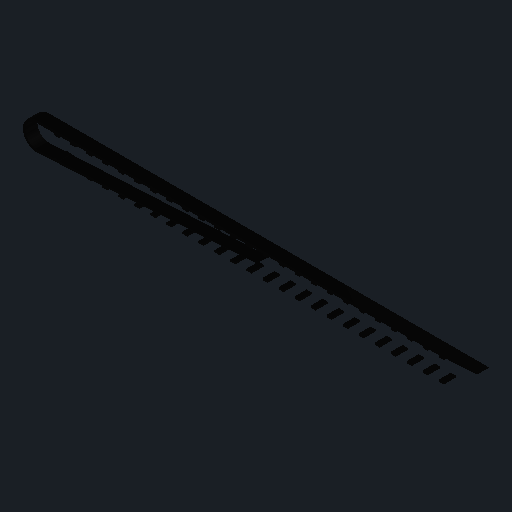
# Autodesk Inventor part: Cinta_Transportadora_20mm_L500
Saved by Autodesk Inventor 2027.2 (Build 312334000, 334)
## iProperties
Part Number: Cinta_Transportadora_20mm_L500
Material: Genérico
Document SubType Name: Modelado
Designer: Usuario
Appearance: Por defecto
Author: Usuario
Autodesk Inventor part; units mm, degrees
ref_plane "Plano YZ" through (0, 0, 0) normal (1, 0, 0) x (0, 1, 0)
ref_plane "Plano XZ" through (0, 0, 0) normal (0, 1, 0) x (-1, 0, 0)
ref_plane "Plano XY" through (0, 0, 0) normal (0, 0, 1) x (1, 0, 0)
sketch "Boceto1" plane through (0, 0, 0) normal (0, 0, 1) x (1, 0, 0)
  line L0 (-220, 14) -> (220, 14)
  arc A0 (220, -14) -> (220, 14) centre (220, 0) ccw
  line L1 (220, 14) -> (-220, -14)
  arc A1 (-220, 14) -> (-220, -14) centre (-220, 0) ccw
  constraints: 4 end point, 4 point on circle, 2 centre point
extrude "Extrusión1" add sketch "Boceto1" along normal mid plane 12
sketch "Boceto2" plane through (0, 0, 0) normal (0, 0, 1) x (1, 0, 0)
  line L0 (-220, 11.5) -> (220, 11.5)
  arc A0 (220, -11.5) -> (220, 11.5) centre (220, 0) ccw
  line L1 (220, 11.5) -> (-220, -11.5)
  arc A1 (-220, 11.5) -> (-220, -11.5) centre (-220, 0) ccw
  constraints: 4 end point, 4 point on circle, 2 centre point
extrude "Extrusión2" cut sketch "Boceto2" along normal mid plane 12
sketch "Boceto3" plane through (0, 0, 0) normal (0, 0, 1) x (1, 0, 0)
  line L0 (-202.5, -11.5) -> (-197.5, -11.5)
  line L1 (-197.5, -11.5) -> (-197.5, -9.7)
  line L2 (-197.5, -9.7) -> (-202.5, -9.7)
  line L3 (-202.5, -9.7) -> (-202.5, -11.5)
  line L4 (-202.5, 9.7) -> (-197.5, 9.7)
  line L5 (-197.5, 9.7) -> (-197.5, 11.5)
  line L6 (-197.5, 11.5) -> (-202.5, 11.5)
  line L7 (-202.5, 11.5) -> (-202.5, 9.7)
  line L8 (-186.5, -11.5) -> (-181.5, -11.5)
  line L9 (-181.5, -11.5) -> (-181.5, -9.7)
  line L10 (-181.5, -9.7) -> (-186.5, -9.7)
  line L11 (-186.5, -9.7) -> (-186.5, -11.5)
  line L12 (-186.5, 9.7) -> (-181.5, 9.7)
  line L13 (-181.5, 9.7) -> (-181.5, 11.5)
  line L14 (-181.5, 11.5) -> (-186.5, 11.5)
  line L15 (-186.5, 11.5) -> (-186.5, 9.7)
  line L16 (-170.5, -11.5) -> (-165.5, -11.5)
  line L17 (-165.5, -11.5) -> (-165.5, -9.7)
  line L18 (-165.5, -9.7) -> (-170.5, -9.7)
  line L19 (-170.5, -9.7) -> (-170.5, -11.5)
  line L20 (-170.5, 9.7) -> (-165.5, 9.7)
  line L21 (-165.5, 9.7) -> (-165.5, 11.5)
  line L22 (-165.5, 11.5) -> (-170.5, 11.5)
  line L23 (-170.5, 11.5) -> (-170.5, 9.7)
  line L24 (-154.5, -11.5) -> (-149.5, -11.5)
  line L25 (-149.5, -11.5) -> (-149.5, -9.7)
  line L26 (-149.5, -9.7) -> (-154.5, -9.7)
  line L27 (-154.5, -9.7) -> (-154.5, -11.5)
  line L28 (-154.5, 9.7) -> (-149.5, 9.7)
  line L29 (-149.5, 9.7) -> (-149.5, 11.5)
  line L30 (-149.5, 11.5) -> (-154.5, 11.5)
  line L31 (-154.5, 11.5) -> (-154.5, 9.7)
  line L32 (-138.5, -11.5) -> (-133.5, -11.5)
  line L33 (-133.5, -11.5) -> (-133.5, -9.7)
  line L34 (-133.5, -9.7) -> (-138.5, -9.7)
  line L35 (-138.5, -9.7) -> (-138.5, -11.5)
  line L36 (-138.5, 9.7) -> (-133.5, 9.7)
  line L37 (-133.5, 9.7) -> (-133.5, 11.5)
  line L38 (-133.5, 11.5) -> (-138.5, 11.5)
  line L39 (-138.5, 11.5) -> (-138.5, 9.7)
  line L40 (-122.5, -11.5) -> (-117.5, -11.5)
  line L41 (-117.5, -11.5) -> (-117.5, -9.7)
  line L42 (-117.5, -9.7) -> (-122.5, -9.7)
  line L43 (-122.5, -9.7) -> (-122.5, -11.5)
  line L44 (-122.5, 9.7) -> (-117.5, 9.7)
  line L45 (-117.5, 9.7) -> (-117.5, 11.5)
  line L46 (-117.5, 11.5) -> (-122.5, 11.5)
  line L47 (-122.5, 11.5) -> (-122.5, 9.7)
  line L48 (-106.5, -11.5) -> (-101.5, -11.5)
  line L49 (-101.5, -11.5) -> (-101.5, -9.7)
  line L50 (-101.5, -9.7) -> (-106.5, -9.7)
  line L51 (-106.5, -9.7) -> (-106.5, -11.5)
  line L52 (-106.5, 9.7) -> (-101.5, 9.7)
  line L53 (-101.5, 9.7) -> (-101.5, 11.5)
  line L54 (-101.5, 11.5) -> (-106.5, 11.5)
  line L55 (-106.5, 11.5) -> (-106.5, 9.7)
  line L56 (-90.5, -11.5) -> (-85.5, -11.5)
  line L57 (-85.5, -11.5) -> (-85.5, -9.7)
  line L58 (-85.5, -9.7) -> (-90.5, -9.7)
  line L59 (-90.5, -9.7) -> (-90.5, -11.5)
  line L60 (-90.5, 9.7) -> (-85.5, 9.7)
  line L61 (-85.5, 9.7) -> (-85.5, 11.5)
  line L62 (-85.5, 11.5) -> (-90.5, 11.5)
  line L63 (-90.5, 11.5) -> (-90.5, 9.7)
  line L64 (-74.5, -11.5) -> (-69.5, -11.5)
  line L65 (-69.5, -11.5) -> (-69.5, -9.7)
  line L66 (-69.5, -9.7) -> (-74.5, -9.7)
  line L67 (-74.5, -9.7) -> (-74.5, -11.5)
  line L68 (-74.5, 9.7) -> (-69.5, 9.7)
  line L69 (-69.5, 9.7) -> (-69.5, 11.5)
  line L70 (-69.5, 11.5) -> (-74.5, 11.5)
  line L71 (-74.5, 11.5) -> (-74.5, 9.7)
  line L72 (-58.5, -11.5) -> (-53.5, -11.5)
  line L73 (-53.5, -11.5) -> (-53.5, -9.7)
  line L74 (-53.5, -9.7) -> (-58.5, -9.7)
  line L75 (-58.5, -9.7) -> (-58.5, -11.5)
  line L76 (-58.5, 9.7) -> (-53.5, 9.7)
  line L77 (-53.5, 9.7) -> (-53.5, 11.5)
  line L78 (-53.5, 11.5) -> (-58.5, 11.5)
  line L79 (-58.5, 11.5) -> (-58.5, 9.7)
  line L80 (-42.5, -11.5) -> (-37.5, -11.5)
  line L81 (-37.5, -11.5) -> (-37.5, -9.7)
  line L82 (-37.5, -9.7) -> (-42.5, -9.7)
  line L83 (-42.5, -9.7) -> (-42.5, -11.5)
  line L84 (-42.5, 9.7) -> (-37.5, 9.7)
  line L85 (-37.5, 9.7) -> (-37.5, 11.5)
  line L86 (-37.5, 11.5) -> (-42.5, 11.5)
  line L87 (-42.5, 11.5) -> (-42.5, 9.7)
  line L88 (-26.5, -11.5) -> (-21.5, -11.5)
  line L89 (-21.5, -11.5) -> (-21.5, -9.7)
  line L90 (-21.5, -9.7) -> (-26.5, -9.7)
  line L91 (-26.5, -9.7) -> (-26.5, -11.5)
  line L92 (-26.5, 9.7) -> (-21.5, 9.7)
  line L93 (-21.5, 9.7) -> (-21.5, 11.5)
  line L94 (-21.5, 11.5) -> (-26.5, 11.5)
  line L95 (-26.5, 11.5) -> (-26.5, 9.7)
  line L96 (-10.5, -11.5) -> (-5.5, -11.5)
  line L97 (-5.5, -11.5) -> (-5.5, -9.7)
  line L98 (-5.5, -9.7) -> (-10.5, -9.7)
  line L99 (-10.5, -9.7) -> (-10.5, -11.5)
  line L100 (-10.5, 9.7) -> (-5.5, 9.7)
  line L101 (-5.5, 9.7) -> (-5.5, 11.5)
  line L102 (-5.5, 11.5) -> (-10.5, 11.5)
  line L103 (-10.5, 11.5) -> (-10.5, 9.7)
  line L104 (5.5, -11.5) -> (10.5, -11.5)
  line L105 (10.5, -11.5) -> (10.5, -9.7)
  line L106 (10.5, -9.7) -> (5.5, -9.7)
  line L107 (5.5, -9.7) -> (5.5, -11.5)
  line L108 (5.5, 9.7) -> (10.5, 9.7)
  line L109 (10.5, 9.7) -> (10.5, 11.5)
  line L110 (10.5, 11.5) -> (5.5, 11.5)
  line L111 (5.5, 11.5) -> (5.5, 9.7)
  line L112 (21.5, -11.5) -> (26.5, -11.5)
  line L113 (26.5, -11.5) -> (26.5, -9.7)
  line L114 (26.5, -9.7) -> (21.5, -9.7)
  line L115 (21.5, -9.7) -> (21.5, -11.5)
  line L116 (21.5, 9.7) -> (26.5, 9.7)
  line L117 (26.5, 9.7) -> (26.5, 11.5)
  line L118 (26.5, 11.5) -> (21.5, 11.5)
  line L119 (21.5, 11.5) -> (21.5, 9.7)
  line L120 (37.5, -11.5) -> (42.5, -11.5)
  line L121 (42.5, -11.5) -> (42.5, -9.7)
  line L122 (42.5, -9.7) -> (37.5, -9.7)
  line L123 (37.5, -9.7) -> (37.5, -11.5)
  line L124 (37.5, 9.7) -> (42.5, 9.7)
  line L125 (42.5, 9.7) -> (42.5, 11.5)
  line L126 (42.5, 11.5) -> (37.5, 11.5)
  line L127 (37.5, 11.5) -> (37.5, 9.7)
  line L128 (53.5, -11.5) -> (58.5, -11.5)
  line L129 (58.5, -11.5) -> (58.5, -9.7)
  line L130 (58.5, -9.7) -> (53.5, -9.7)
  line L131 (53.5, -9.7) -> (53.5, -11.5)
  line L132 (53.5, 9.7) -> (58.5, 9.7)
  line L133 (58.5, 9.7) -> (58.5, 11.5)
  line L134 (58.5, 11.5) -> (53.5, 11.5)
  line L135 (53.5, 11.5) -> (53.5, 9.7)
  line L136 (69.5, -11.5) -> (74.5, -11.5)
  line L137 (74.5, -11.5) -> (74.5, -9.7)
  line L138 (74.5, -9.7) -> (69.5, -9.7)
  line L139 (69.5, -9.7) -> (69.5, -11.5)
  line L140 (69.5, 9.7) -> (74.5, 9.7)
  line L141 (74.5, 9.7) -> (74.5, 11.5)
  line L142 (74.5, 11.5) -> (69.5, 11.5)
  line L143 (69.5, 11.5) -> (69.5, 9.7)
  line L144 (85.5, -11.5) -> (90.5, -11.5)
  line L145 (90.5, -11.5) -> (90.5, -9.7)
  line L146 (90.5, -9.7) -> (85.5, -9.7)
  line L147 (85.5, -9.7) -> (85.5, -11.5)
  line L148 (85.5, 9.7) -> (90.5, 9.7)
  line L149 (90.5, 9.7) -> (90.5, 11.5)
  line L150 (90.5, 11.5) -> (85.5, 11.5)
  line L151 (85.5, 11.5) -> (85.5, 9.7)
  line L152 (101.5, -11.5) -> (106.5, -11.5)
  line L153 (106.5, -11.5) -> (106.5, -9.7)
  line L154 (106.5, -9.7) -> (101.5, -9.7)
  line L155 (101.5, -9.7) -> (101.5, -11.5)
  line L156 (101.5, 9.7) -> (106.5, 9.7)
  line L157 (106.5, 9.7) -> (106.5, 11.5)
  line L158 (106.5, 11.5) -> (101.5, 11.5)
  line L159 (101.5, 11.5) -> (101.5, 9.7)
  line L160 (117.5, -11.5) -> (122.5, -11.5)
  line L161 (122.5, -11.5) -> (122.5, -9.7)
  line L162 (122.5, -9.7) -> (117.5, -9.7)
  line L163 (117.5, -9.7) -> (117.5, -11.5)
  line L164 (117.5, 9.7) -> (122.5, 9.7)
  line L165 (122.5, 9.7) -> (122.5, 11.5)
  line L166 (122.5, 11.5) -> (117.5, 11.5)
  line L167 (117.5, 11.5) -> (117.5, 9.7)
  line L168 (133.5, -11.5) -> (138.5, -11.5)
  line L169 (138.5, -11.5) -> (138.5, -9.7)
  line L170 (138.5, -9.7) -> (133.5, -9.7)
  line L171 (133.5, -9.7) -> (133.5, -11.5)
  line L172 (133.5, 9.7) -> (138.5, 9.7)
  line L173 (138.5, 9.7) -> (138.5, 11.5)
  line L174 (138.5, 11.5) -> (133.5, 11.5)
  line L175 (133.5, 11.5) -> (133.5, 9.7)
  line L176 (149.5, -11.5) -> (154.5, -11.5)
  line L177 (154.5, -11.5) -> (154.5, -9.7)
  line L178 (154.5, -9.7) -> (149.5, -9.7)
  line L179 (149.5, -9.7) -> (149.5, -11.5)
  line L180 (149.5, 9.7) -> (154.5, 9.7)
  line L181 (154.5, 9.7) -> (154.5, 11.5)
  line L182 (154.5, 11.5) -> (149.5, 11.5)
  line L183 (149.5, 11.5) -> (149.5, 9.7)
  line L184 (165.5, -11.5) -> (170.5, -11.5)
  line L185 (170.5, -11.5) -> (170.5, -9.7)
  line L186 (170.5, -9.7) -> (165.5, -9.7)
  line L187 (165.5, -9.7) -> (165.5, -11.5)
  line L188 (165.5, 9.7) -> (170.5, 9.7)
  line L189 (170.5, 9.7) -> (170.5, 11.5)
  line L190 (170.5, 11.5) -> (165.5, 11.5)
  line L191 (165.5, 11.5) -> (165.5, 9.7)
  line L192 (181.5, -11.5) -> (186.5, -11.5)
  line L193 (186.5, -11.5) -> (186.5, -9.7)
  line L194 (186.5, -9.7) -> (181.5, -9.7)
  line L195 (181.5, -9.7) -> (181.5, -11.5)
  line L196 (181.5, 9.7) -> (186.5, 9.7)
  line L197 (186.5, 9.7) -> (186.5, 11.5)
  line L198 (186.5, 11.5) -> (181.5, 11.5)
  line L199 (181.5, 11.5) -> (181.5, 9.7)
  constraints: 400 end point, 100 parallel, 50 horizontal, 50 perpendicular
extrude "Extrusión3" add sketch "Boceto3" along normal mid plane 12
